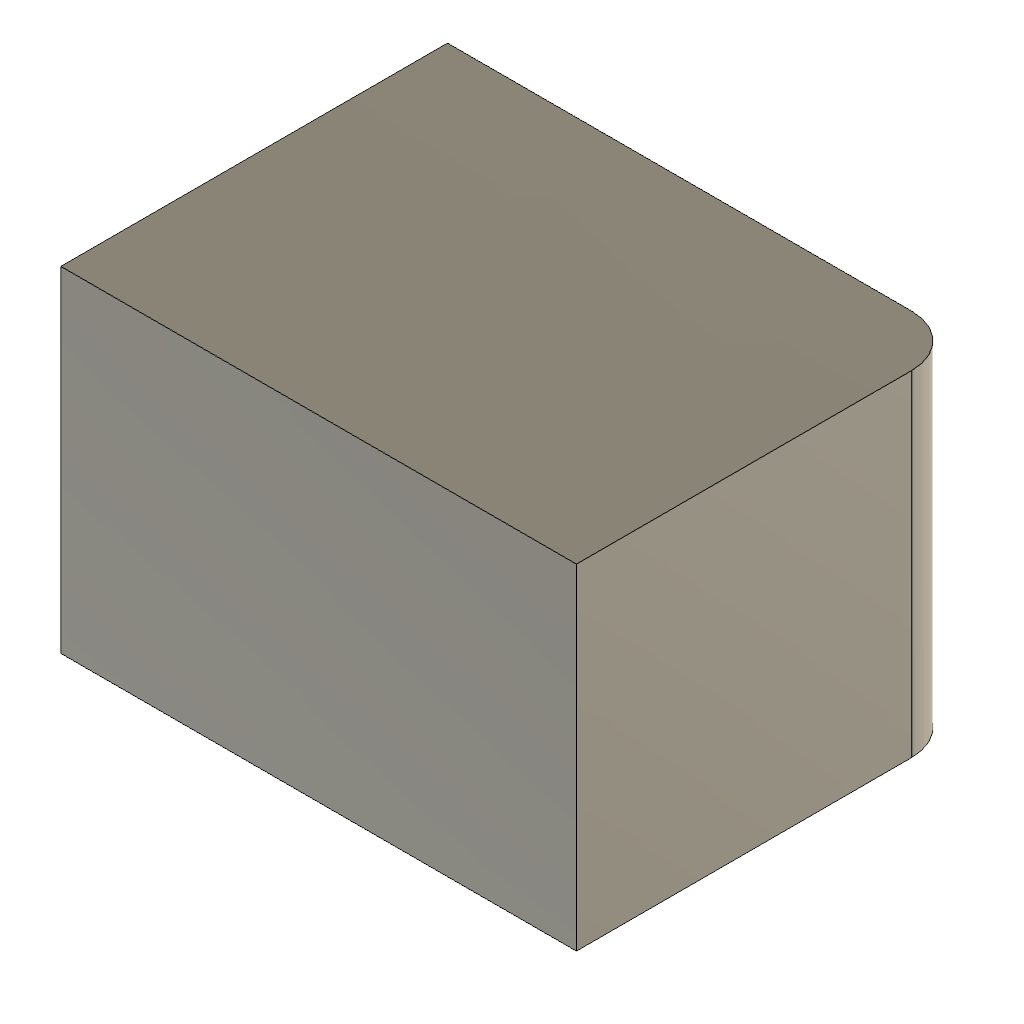
vendor_ConstructionPart (Autodesk Fusion 360 design; units mm, degrees)
Autodesk Fusion 360 part; units mm, degrees
sketch "Base sketch" plane through (0, 0, 0) normal (0, 0, 1) x (1, 0, 0)
  line L0 (0, 0) -> (40, 0)
  line L1 (40, 0) -> (40, 30)
  line L2 (40, 30) -> (0, 30)
  line L3 (0, 30) -> (0, 0)
extrude "Base extrude" add sketch "Base sketch" along normal blind 26
sketch "Pocket sketch" plane through (0, 0, 0) normal (0, 0, 1) x (1, 0, 0)
  circle A0 centre (8, 8) radius 3
extrude "Pocket extrude" cut sketch "Pocket sketch" along normal blind 20
fillet "Corner round" radius 4 1 edges at (40, 30, 13)
equation "height = 20.0 mm"
